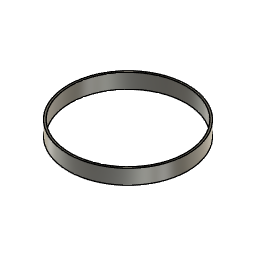
scianka boczna v1 (Autodesk Fusion 360 design; units mm, degrees)
Autodesk Fusion 360 part; units mm, degrees
sketch "Szkic1" plane through (0, 0, 0) normal (0, 0, 1) x (1, 0, 0)
  circle A0 centre (0, 0) radius 65
  circle A1 centre (0, 0) radius 64
  dimension "d1" = 130
  dimension "d2" = 128
  constraint coincident A0.centre A1.centre
  measures "d1" diameter of A0
  measures "d2" diameter of A1
extrude "Wyciągnięcie proste1" add sketch "Szkic1" along normal blind 11
extrude "Wyciągnięcie proste2" add 1 faces at (63.2238, 12.7952, 11) along direction (0, 0, 1) blind 5
move_face "Odsuń powierzchnie1" offset 1 1 faces at (-63.682, -6.3723, 5.3333)
sketch "Szkic2" plane through (0, 0, 0) normal (0, 0, 1) x (1, 0, 0)
